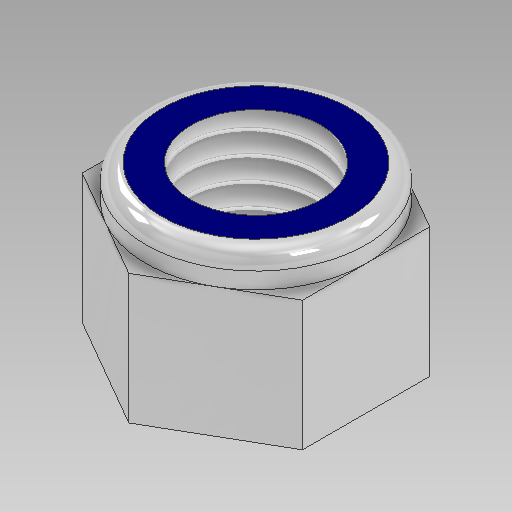
# Autodesk Inventor part: M4_Nylon-nut
Saved by Autodesk Inventor 2025 (Build 290162000, 162)
## iProperties
Created: 2024-11-08
Part Number: M4_Nylon-nut
Material: 일반
Document SubType Name: Modeling
Designer: OSB
Density: 1 g/cm^3
Appearance: 기본값
Author: OSB
Autodesk Inventor part; units mm, degrees
ref_plane "YZ Plane" through (0, 0, 0) normal (1, 0, 0) x (0, 1, 0)
ref_plane "XZ Plane" through (0, 0, 0) normal (0, 1, 0) x (-1, 0, 0)
ref_plane "XY Plane" through (0, 0, 0) normal (0, 0, 1) x (1, 0, 0)
sketch "스케치1" plane through (0, 0, 0) normal (0, 0, 1) x (1, 0, 0)
  line L0 (-3.926, 0) -> (-1.963, 3.4)
  line L1 (-1.963, 3.4) -> (1.963, 3.4)
  line L2 (1.963, 3.4) -> (3.926, 0)
  line L3 (3.926, 0) -> (1.963, -3.4)
  line L4 (1.963, -3.4) -> (-1.963, -3.4)
  line L5 (-1.963, -3.4) -> (-3.926, 0)
  circle A0 centre (0, 0) radius 2
  circle A1 centre (0, 0) radius 3.4
  circle A2 centre (0, 0) radius 2.9
  point P0 (-2.9445, -1.7)
  point P1 (-2.9445, 1.7)
  point P2 (0, 3.4)
  point P3 (2.9445, 1.7)
  point P4 (2.9445, -1.7)
  point P5 (0, -3.4)
  dimension "d0" = 6.8
  dimension "d1" = 4
  dimension "d2" = 0.5
  constraints: 12 end point, 3 centre point, 3 coincident, 1 horizontal alignment, 1 tangent, 13 other
  measures "d0" distance between parallel lines of L1 L4
  measures "d1" diameter of A0
  measures "d2" radial gap between concentric circles of A1 A2
extrude "돌출1" add sketch "스케치1" along normal blind 4 contours L0 A1 L5 | L0 L1 A1 | A1 | A1 L4 L5 | L1 L2 A1 | A1 L3 L4 | L2 L3 A1 | A2
extrude "돌출3" add sketch "스케치1" along normal blind 1 from surface at 4 contours A1 | A2
fillet "모깎기1" radius 0.5 1 edges at (-3.4, 0, 5)
thread "스레드1" size "M4x0.7" class "6H" standard "ANSI Metric M Profile" full length
